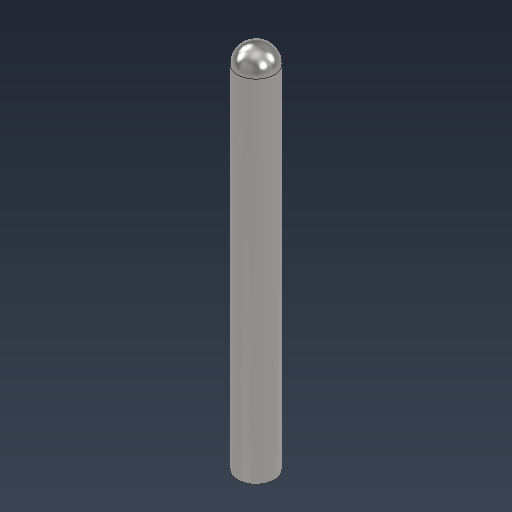
# Autodesk Inventor part: 부품2
Saved by Autodesk Inventor 2026.2 (Build 302298010, 298A)
## iProperties
Created: 2026-04-09
Part Number: 부품2
Material: 스테인리스스틸
Document SubType Name: Modeling
Designer: khw
Density: 8 g/cm^3
Appearance: 반연마
Description: 편단 M3 위치고정핀 외경 4, 길이 40
Mass: 3.27035 g
Surface Area: 6.54274 cm^2
Volume: 0.408794 cm^3
Author: khw
Autodesk Inventor part; units mm, degrees
ref_plane "YZ Plane" through (0, 0, 0) normal (1, 0, 0) x (0, 1, 0)
ref_plane "XZ Plane" through (0, 0, 0) normal (0, 1, 0) x (-1, 0, 0)
ref_plane "XY Plane" through (0, 0, 0) normal (0, 0, 1) x (1, 0, 0)
sketch "스케치1" plane through (0, 0, 0) normal (0, 1, 0) x (-1, 0, 0)
  circle A0 centre (0, 0) radius 2
  dimension "d0" = 4
  constraints: 1 centre point, 1 coincident
  measures "d0" diameter of A0
extrude "돌출1" add sketch "스케치1" along normal blind 40
fillet "모깎기1" radius 2 1 edges at (2, 40, 0)
sketch "스케치2" plane through (0, 0, 0) normal (0, -1, 0) x (1, 0, 0)
  circle A0 centre (0, 0) radius 2 projected
  constraints: 1 coincident
hole "구멍1" at (0, 0, 0) direction (0, 1, 0) diameter 2.459 depth 18 thread size "M3x0.5" class "6H" standard "ISO Metric profile"
